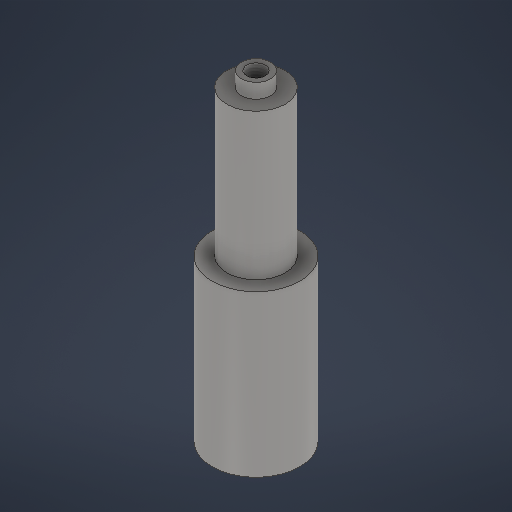
# Autodesk Inventor part: Connecting Rod (Final Project)
Saved by Autodesk Inventor 2026 (Build 300175000, 175)
## iProperties
Created: 2025-12-01
Part Number: Connecting Rod (Final Project)
Material: Stainless Steel
Document SubType Name: Modeling
Designer: gmz
Density: 8 g/cm^3
Appearance: Semi-Polished
Author: gmz
Autodesk Inventor part; units mm, degrees
ref_plane "YZ Plane" through (0, 0, 0) normal (1, 0, 0) x (0, 1, 0)
ref_plane "XZ Plane" through (0, 0, 0) normal (0, 1, 0) x (-1, 0, 0)
ref_plane "XY Plane" through (0, 0, 0) normal (0, 0, 1) x (1, 0, 0)
sketch "Sketch1" plane through (0, 0, 0) normal (0, 0, 1) x (1, 0, 0)
  line L0 (0, 301.5322) -> (12.7, 301.5322)
  line L1 (12.7, 301.5322) -> (12.7, 288.8322)
  line L2 (12.7, 288.8322) -> (25.4, 288.8322)
  line L3 (25.4, 288.8322) -> (25.4, 161.8322)
  line L4 (25.4, 161.8322) -> (38.1, 161.8322)
  line L5 (38.1, 161.8322) -> (38.1, 22.1322)
  line L6 (38.1, 22.1322) -> (0, 22.1322)
  line L7 (0, 301.5322) -> (0, 22.1322)
  line L8 (0, -60.3064) -> (0, 361.8387) projected
  point P0 (0, 0)
  dimension "d0" = 12.7
  dimension "d1" = 12.7
  dimension "d2" = 12.7
  dimension "d4" = 127
  dimension "d5" = 12.7
  dimension "d6" = 139.7
  dimension "d10" = 38.1
  dimension "d11" = 38.1
  dimension "d12" = 161.8322
  constraints: 16 end point, 3 perpendicular, 2 horizontal, 2 vertical
  measures "d0" distance of L0.start L0.end
  measures "d1" distance of L0.end L1.end
  measures "d2" distance of L1.end L2.end
  measures "d4" distance of L2.end L3.end
  measures "d5" distance of L3.end L4.end
  measures "d6" distance of L4.end L5.end
  measures "d10" distance of L5.end L6.end
  measures "d11" distance from line of point (0, 0) L5
  measures "d12" distance from line of point (0, 0) L4
revolve "Revolution1" add sketch "Sketch1" angle 360 about axis through (0, -10, 0) along (0, 1, 0)
sketch "Sketch4" plane through (0, 22.1322, 0) normal (0, -1, 0) x (1, 0, 0)
  circle A0 centre (0, 0) radius 8.89 projected
  constraints: 1 coincident
hole "Hole1" at (0, 22.1322, 0) direction (0, 1, 0) diameter 16.3068 depth 12.7 tip angle 118 thread size "3/4-10 UNC" class "2B" standard "ANSI Unified Screw Threads"
sketch "Sketch5" plane through (0, 301.5322, 0) normal (0, 1, 0) x (1, 0, 0)
  circle A0 centre (0, 0) radius 12.7
  constraints: 1 centre point, 1 coincident
hole "Hole2" at (0, 301.5322, 0) direction (0, -1, 0) diameter 16.3068 depth 25.4 tip angle 118 thread size "3/4-10 UNC" class "2B" standard "ANSI Unified Screw Threads"
body "Solid1"
